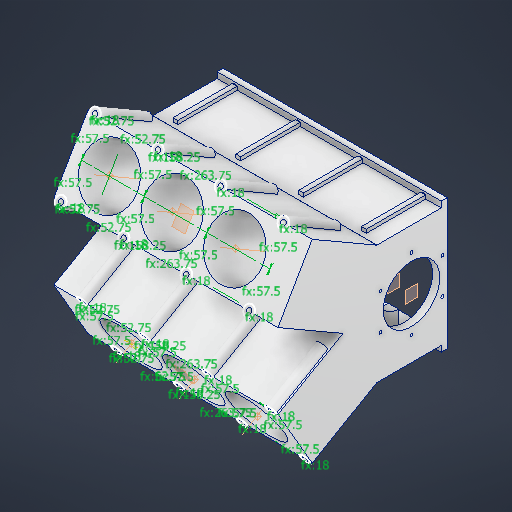
# Autodesk Inventor part: V6_Engine_Block
Saved by Autodesk Inventor 2027.1 (Build 311270010, 270A)
## iProperties
Created: 2026-10-17
Part Number: V6_Engine_Block
Material: Aluminum 6061
Document SubType Name: Modeling
Designer: kashyap
Density: 2.7 g/cm^3
Appearance: Aluminum - Flat
Mass: 21901.2 g
Surface Area: 10450.8 cm^2
Volume: 8111.54 cm^3
Material_Status: Assumed for this reconstruction
Author: kashyap
Autodesk Inventor part; units mm, degrees
ref_plane "YZ Plane" through (0, 0, 0) normal (1, 0, 0) x (0, 1, 0)
derived "V6_Engine_Master.ipt"
ref_plane "Bank_A_Plane" through (0, 0, 0) normal (0, 0.8660254, -0.5) x (-1, 0, 0)
ref_plane "Bank_B_Plane" through (0, 0, 0) normal (0, 0.8660254, 0.5) x (-1, 0, 0)
ref_plane "Bank_A_Perp_Plane" through (0, 0, 0) normal (0, 0.5, 0.8660254) x (-1, 0, 0)
ref_plane "Bank_B_Perp_Plane" through (0, 0, 0) normal (0, -0.5, 0.8660254) x (-1, 0, 0)
ref_plane "Bank_A_Deck_Plane" through (0, 112.9, 195.5485) normal (0, 0.5, 0.8660254) x (-1, 0, 0)
ref_plane "Bank_B_Deck_Plane" through (0, -112.9, 195.5485) normal (0, -0.5, 0.8660254) x (-1, 0, 0)
ref_plane "Cyl_A1_Station_Plane" through (-123.8, 0, 0) normal (1, 0, 0) x (0, 1, 0)
ref_plane "Cyl_A2_Station_Plane" through (-18.3, 0, 0) normal (1, 0, 0) x (0, 1, 0)
ref_plane "Cyl_A3_Station_Plane" through (87.2, 0, 0) normal (1, 0, 0) x (0, 1, 0)
ref_plane "Cyl_B1_Station_Plane" through (-87.2, 0, 0) normal (1, 0, 0) x (0, 1, 0)
ref_plane "Cyl_B2_Station_Plane" through (18.3, 0, 0) normal (1, 0, 0) x (0, 1, 0)
ref_plane "Cyl_B3_Station_Plane" through (123.8, 0, 0) normal (1, 0, 0) x (0, 1, 0)
ref_plane "Main_Bearing_Station_1" through (-158.25, 0, 0) normal (1, 0, 0) x (0, 1, 0)
ref_plane "Main_Bearing_Station_2" through (-52.75, 0, 0) normal (1, 0, 0) x (0, 1, 0)
ref_plane "Main_Bearing_Station_3" through (52.75, 0, 0) normal (1, 0, 0) x (0, 1, 0)
ref_plane "Main_Bearing_Station_4" through (158.25, 0, 0) normal (1, 0, 0) x (0, 1, 0)
ref_plane "Front_Interface" through (-188.25, 0, 0) normal (1, 0, 0) x (0, 1, 0)
ref_plane "Rear_Interface" through (188.25, 0, 0) normal (1, 0, 0) x (0, 1, 0)
ref_plane "Oil_Pan_Plane" through (0, 0, -60) normal (0, 0, 1) x (1, 0, 0)
sketch "SK_Bank_A_Prism" plane through (-188.25, 0, 0) normal (1, 0, 0) x (0, 1, 0)
  line L0 (170.3375, 295.0332) -> (-57.4375, -99.4847) construction
  line L1 (-188.26, 108.692) -> (188.26, -108.692) construction
  line L2 (-75.36, 304.2405) -> (301.16, 86.8565) construction
  line L3 (49.7965, -28.75) -> (162.6965, 166.7985)
  line L4 (162.6965, 166.7985) -> (63.1035, 224.2985)
  line L5 (63.1035, 224.2985) -> (-49.7965, 28.75)
  line L6 (-49.7965, 28.75) -> (49.7965, -28.75)
  dimension "d19" = 57.5
  dimension "d20" = 57.5
  constraints: 8 end point, 2 collinear, 2 parallel
  measures "d19" distance between parallel lines of L3 L0
  measures "d20" distance between parallel lines of L5 L0
extrude "Bank_A_Prism" add sketch "SK_Bank_A_Prism" along normal up to surface (376.5 mm away)
sketch "SK_Bank_B_Prism" plane through (-188.25, 0, 0) normal (1, 0, 0) x (0, 1, 0)
  line L0 (-170.3375, 295.0332) -> (57.4375, -99.4847) construction
  line L1 (-188.26, -108.692) -> (188.26, 108.692) construction
  line L2 (-301.16, 86.8565) -> (75.36, 304.2405) construction
  line L3 (-49.7965, -28.75) -> (-162.6965, 166.7985)
  line L4 (-162.6965, 166.7985) -> (-63.1035, 224.2985)
  line L5 (-63.1035, 224.2985) -> (49.7965, 28.75)
  line L6 (49.7965, 28.75) -> (-49.7965, -28.75)
  dimension "d23" = 57.5
  dimension "d24" = 57.5
  constraints: 8 end point, 2 collinear, 2 parallel
  measures "d23" distance between parallel lines of L3 L0
  measures "d24" distance between parallel lines of L5 L0
extrude "Bank_B_Prism" add sketch "SK_Bank_B_Prism" along normal up to surface (376.5 mm away)
sketch "SK_Crankcase_Prism" plane through (-188.25, 0, 0) normal (1, 0, 0) x (0, 1, 0)
  line L0 (-140, -60) -> (140, -60) construction
  line L1 (-100, -60) -> (100, -60)
  line L2 (100, -60) -> (100, 58)
  line L3 (100, 58) -> (-100, 58)
  line L4 (-100, 58) -> (-100, -60)
  point P0 (0, 0)
  dimension "d30" = 100
  dimension "d31" = 100
  dimension "d32" = 118
  constraints: 8 end point, 2 horizontal, 2 vertical, 1 collinear
  measures "d30" horizontal distance of point (0, 0) L1.end
  measures "d31" horizontal distance of point (0, 0) L3.end
  measures "d32" distance between parallel lines of L3 L0
extrude "Crankcase_Prism" add sketch "SK_Crankcase_Prism" along normal up to surface (376.5 mm away)
sketch "SK_Oil_Pan_Flange" plane through (-188.25, 0, 0) normal (1, 0, 0) x (0, 1, 0)
  line L0 (-154, -60) -> (154, -60) construction
  line L1 (-110, -60) -> (110, -60)
  line L2 (110, -60) -> (110, -50)
  line L3 (110, -50) -> (-110, -50)
  line L4 (-110, -50) -> (-110, -60)
  point P0 (0, 0)
  dimension "d35" = 110
  dimension "d36" = 110
  dimension "d37" = 10
  constraints: 8 end point, 2 horizontal, 2 vertical, 1 collinear
  measures "d35" horizontal distance of point (0, 0) L1.end
  measures "d36" horizontal distance of point (0, 0) L3.end
  measures "d37" distance between parallel lines of L3 L0
extrude "Oil_Pan_Flange" add sketch "SK_Oil_Pan_Flange" along normal up to surface (376.5 mm away)
ref_plane "Front_Wall_Inner_Plane" through (-176.25, 0, 0) normal (1, 0, 0) x (0, 1, 0)
ref_plane "Rear_Wall_Inner_Plane" through (176.25, 0, 0) normal (1, 0, 0) x (0, 1, 0)
sketch "SK_Cavity_Lower" plane through (-176.25, 0, 0) normal (1, 0, 0) x (0, 1, 0)
  line L0 (-131.6, -60) -> (131.6, -60) construction
  line L1 (-94, -60) -> (94, -60)
  line L2 (94, -60) -> (94, 45)
  line L3 (94, 45) -> (-94, 45)
  line L4 (-94, 45) -> (-94, -60)
  point P0 (0, 0)
  dimension "d42" = 94
  dimension "d43" = 94
  dimension "d44" = 105
  constraints: 8 end point, 2 horizontal, 2 vertical, 1 collinear
  measures "d42" horizontal distance of point (0, 0) L1.end
  measures "d43" horizontal distance of point (0, 0) L3.end
  measures "d44" distance between parallel lines of L3 L0
extrude "Cavity_Lower" cut sketch "SK_Cavity_Lower" along normal up to surface (352.5 mm away)
sketch "SK_Cavity_Under_Bank_A" plane through (-176.25, 0, 0) normal (1, 0, 0) x (0, 1, 0)
  line L0 (82.9722, 143.7121) -> (-37.5722, -65.077) construction
  line L1 (-104.6545, 60.4223) -> (104.6545, -60.4223) construction
  line L2 (40.7032, -23.5) -> (86.1032, 55.1351)
  line L3 (86.1032, 55.1351) -> (4.6968, 102.1351)
  line L4 (4.6968, 102.1351) -> (-40.7032, 23.5)
  line L5 (-40.7032, 23.5) -> (40.7032, -23.5)
  dimension "d47" = 47
  dimension "d48" = 47
  dimension "d49" = 90.8
  constraints: 8 end point, 3 parallel, 1 collinear
  measures "d47" distance between parallel lines of L2 L0
  measures "d48" distance between parallel lines of L4 L0
  measures "d49" distance between parallel lines of L3 L1
extrude "Cavity_Under_Bank_A" cut sketch "SK_Cavity_Under_Bank_A" along normal up to surface (352.5 mm away)
sketch "SK_Cavity_Under_Bank_B" plane through (-176.25, 0, 0) normal (1, 0, 0) x (0, 1, 0)
  line L0 (-82.9722, 143.7121) -> (37.5722, -65.077) construction
  line L1 (-104.6545, -60.4223) -> (104.6545, 60.4223) construction
  line L2 (-40.7032, -23.5) -> (-86.1032, 55.1351)
  line L3 (-86.1032, 55.1351) -> (-4.6968, 102.1351)
  line L4 (-4.6968, 102.1351) -> (40.7032, 23.5)
  line L5 (40.7032, 23.5) -> (-40.7032, -23.5)
  dimension "d52" = 47
  dimension "d53" = 47
  dimension "d54" = 90.8
  constraints: 8 end point, 3 parallel, 1 collinear
  measures "d52" distance between parallel lines of L2 L0
  measures "d53" distance between parallel lines of L4 L0
  measures "d54" distance between parallel lines of L3 L1
extrude "Cavity_Under_Bank_B" cut sketch "SK_Cavity_Under_Bank_B" along normal up to surface (352.5 mm away)
sketch "SK_Main_Web_1" plane through (-158.25, 0, 0) normal (1, 0, 0) x (0, 1, 0)
  line L0 (-131.6, 0) -> (131.6, 0) construction
  line L1 (-94, 0) -> (-33.015, 0)
  line L2 (33.015, 0) -> (94, 0)
  line L3 (94, 0) -> (94, 110)
  line L4 (94, 110) -> (-94, 110)
  line L5 (-94, 110) -> (-94, 0)
  arc A0 (33.015, 0) -> (-33.015, 0) centre (0, 0) ccw
  dimension "d57" = 33.015
  dimension "d58" = 94
  dimension "d59" = 94
  dimension "d60" = 110
  constraints: 10 end point, 2 collinear, 2 point on circle, 2 vertical, 1 centre point, 1 coincident, 1 horizontal
  measures "d57" radius of A0
  measures "d58" distance of point (0, 0) L2.end
  measures "d59" distance of point (0, 0) L1.start
  measures "d60" distance between parallel lines of L4 L0
extrude "Main_Web_1" add sketch "SK_Main_Web_1" along normal mid plane 17
sketch "SK_Main_Web_2" plane through (-52.75, 0, 0) normal (1, 0, 0) x (0, 1, 0)
  line L0 (-131.6, 0) -> (131.6, 0) construction
  line L1 (-94, 0) -> (-33.015, 0)
  line L2 (33.015, 0) -> (94, 0)
  line L3 (94, 0) -> (94, 110)
  line L4 (94, 110) -> (-94, 110)
  line L5 (-94, 110) -> (-94, 0)
  arc A0 (33.015, 0) -> (-33.015, 0) centre (0, 0) ccw
  dimension "d63" = 33.015
  dimension "d64" = 94
  dimension "d65" = 94
  dimension "d66" = 110
  constraints: 10 end point, 2 collinear, 2 point on circle, 2 vertical, 1 centre point, 1 coincident, 1 horizontal
  measures "d63" radius of A0
  measures "d64" distance of point (0, 0) L2.end
  measures "d65" distance of point (0, 0) L1.start
  measures "d66" distance between parallel lines of L4 L0
extrude "Main_Web_2" add sketch "SK_Main_Web_2" along normal mid plane 17
sketch "SK_Main_Web_3" plane through (52.75, 0, 0) normal (1, 0, 0) x (0, 1, 0)
  line L0 (-131.6, 0) -> (131.6, 0) construction
  line L1 (-94, 0) -> (-33.015, 0)
  line L2 (33.015, 0) -> (94, 0)
  line L3 (94, 0) -> (94, 110)
  line L4 (94, 110) -> (-94, 110)
  line L5 (-94, 110) -> (-94, 0)
  arc A0 (33.015, 0) -> (-33.015, 0) centre (0, 0) ccw
  dimension "d69" = 33.015
  dimension "d70" = 94
  dimension "d71" = 94
  dimension "d72" = 110
  constraints: 10 end point, 2 collinear, 2 point on circle, 2 vertical, 1 centre point, 1 coincident, 1 horizontal
  measures "d69" radius of A0
  measures "d70" distance of point (0, 0) L2.end
  measures "d71" distance of point (0, 0) L1.start
  measures "d72" distance between parallel lines of L4 L0
extrude "Main_Web_3" add sketch "SK_Main_Web_3" along normal mid plane 17
sketch "SK_Main_Web_4" plane through (158.25, 0, 0) normal (1, 0, 0) x (0, 1, 0)
  line L0 (-131.6, 0) -> (131.6, 0) construction
  line L1 (-94, 0) -> (-33.015, 0)
  line L2 (33.015, 0) -> (94, 0)
  line L3 (94, 0) -> (94, 110)
  line L4 (94, 110) -> (-94, 110)
  line L5 (-94, 110) -> (-94, 0)
  arc A0 (33.015, 0) -> (-33.015, 0) centre (0, 0) ccw
  dimension "d75" = 33.015
  dimension "d76" = 94
  dimension "d77" = 94
  dimension "d78" = 110
  constraints: 10 end point, 2 collinear, 2 point on circle, 2 vertical, 1 centre point, 1 coincident, 1 horizontal
  measures "d75" radius of A0
  measures "d76" distance of point (0, 0) L2.end
  measures "d77" distance of point (0, 0) L1.start
  measures "d78" distance between parallel lines of L4 L0
extrude "Main_Web_4" add sketch "SK_Main_Web_4" along normal mid plane 17
sketch "SK_Bores_Bank_A" plane through (-18.3, 112.9, 195.5485) normal (0, 0.5, 0.8660254) x (1, 0, 0)
  circle A0 centre (-105.5, 0) radius 47
  circle A1 centre (0, 0) radius 47
  circle A2 centre (105.5, 0) radius 47
  dimension "d81" = 94
  dimension "d82" = 94
  dimension "d83" = 94
  constraints: 3 centre point, 3 coincident
  measures "d81" diameter of A0
  measures "d82" diameter of A1
  measures "d83" diameter of A2
extrude "Bores_Bank_A" cut sketch "SK_Bores_Bank_A" against normal blind 150
sketch "SK_Bores_Bank_B" plane through (18.3, -112.9, 195.5485) normal (0, -0.5, 0.8660254) x (1, 0, 0)
  circle A0 centre (-105.5, 0) radius 47
  circle A1 centre (0, 0) radius 47
  circle A2 centre (105.5, 0) radius 47
  dimension "d86" = 94
  dimension "d87" = 94
  dimension "d88" = 94
  constraints: 3 centre point, 3 coincident
  measures "d86" diameter of A0
  measures "d87" diameter of A1
  measures "d88" diameter of A2
extrude "Bores_Bank_B" cut sketch "SK_Bores_Bank_B" against normal blind 150
sketch "SK_Head_Bolts_Bank_A" plane through (-18.3, 112.9, 195.5485) normal (0, 0.5, 0.8660254) x (1, 0, 0)
  circle A0 centre (-158.25, 57.5) radius 9
  circle A1 centre (-158.25, -57.5) radius 9
  circle A2 centre (-52.75, 57.5) radius 9
  circle A3 centre (-52.75, -57.5) radius 9
  circle A4 centre (52.75, 57.5) radius 9
  circle A5 centre (52.75, -57.5) radius 9
  circle A6 centre (158.25, 57.5) radius 9
  circle A7 centre (158.25, -57.5) radius 9
  point P0 (-105.5, 0)
  dimension "d93" = 18
  dimension "d96" = 18
  dimension "d99" = 18
  dimension "d102" = 18
  dimension "d105" = 18
  dimension "d108" = 18
  dimension "d111" = 18
  dimension "d114" = 18
  dimension "d157" = 52.75
  dimension "d158" = 57.5
  dimension "d159" = 52.75
  dimension "d160" = 57.5
  dimension "d161" = 52.75
  dimension "d162" = 57.5
  dimension "d163" = 52.75
  dimension "d164" = 57.5
  dimension "d165" = 158.25
  dimension "d166" = 57.5
  dimension "d167" = 158.25
  dimension "d168" = 57.5
  dimension "d169" = 263.75
  dimension "d170" = 57.5
  dimension "d171" = 263.75
  dimension "d172" = 57.5
  constraints: 8 centre point
  measures "d93" diameter of A0
  measures "d96" diameter of A1
  measures "d99" diameter of A2
  measures "d102" diameter of A3
  measures "d105" diameter of A4
  measures "d108" diameter of A5
  measures "d111" diameter of A6
  measures "d114" diameter of A7
  measures "d157" horizontal distance of point (-105.5, 0) A0.centre
  measures "d158" vertical distance of point (-105.5, 0) A0.centre
  measures "d159" horizontal distance of point (-105.5, 0) A1.centre
  measures "d160" vertical distance of point (-105.5, 0) A1.centre
  measures "d161" horizontal distance of point (-105.5, 0) A2.centre
  measures "d162" vertical distance of point (-105.5, 0) A2.centre
  measures "d163" horizontal distance of point (-105.5, 0) A3.centre
  measures "d164" vertical distance of point (-105.5, 0) A3.centre
  measures "d165" horizontal distance of point (-105.5, 0) A4.centre
  measures "d166" vertical distance of point (-105.5, 0) A4.centre
  measures "d167" horizontal distance of point (-105.5, 0) A5.centre
  measures "d168" vertical distance of point (-105.5, 0) A5.centre
  measures "d169" horizontal distance of point (-105.5, 0) A6.centre
  measures "d170" vertical distance of point (-105.5, 0) A6.centre
  measures "d171" horizontal distance of point (-105.5, 0) A7.centre
  measures "d172" vertical distance of point (-105.5, 0) A7.centre
extrude "Head_Bolt_Bosses_Bank_A" add sketch "SK_Head_Bolts_Bank_A" against normal blind 100
sketch "SK_Head_Bolts_Bank_B" plane through (18.3, -112.9, 195.5485) normal (0, -0.5, 0.8660254) x (1, 0, 0)
  circle A0 centre (-158.25, -57.5) radius 9
  circle A1 centre (-158.25, 57.5) radius 9
  circle A2 centre (-52.75, -57.5) radius 9
  circle A3 centre (-52.75, 57.5) radius 9
  circle A4 centre (52.75, -57.5) radius 9
  circle A5 centre (52.75, 57.5) radius 9
  circle A6 centre (158.25, -57.5) radius 9
  circle A7 centre (158.25, 57.5) radius 9
  point P0 (-105.5, 0)
  dimension "d126" = 18
  dimension "d129" = 18
  dimension "d132" = 18
  dimension "d135" = 18
  dimension "d138" = 18
  dimension "d141" = 18
  dimension "d144" = 18
  dimension "d147" = 18
  dimension "d196" = 52.75
  dimension "d197" = 57.5
  dimension "d198" = 52.75
  dimension "d199" = 57.5
  dimension "d200" = 52.75
  dimension "d201" = 57.5
  dimension "d202" = 52.75
  dimension "d203" = 57.5
  dimension "d204" = 158.25
  dimension "d205" = 57.5
  dimension "d206" = 158.25
  dimension "d207" = 57.5
  dimension "d208" = 263.75
  dimension "d209" = 57.5
  dimension "d210" = 263.75
  dimension "d211" = 57.5
  constraints: 8 centre point
  measures "d126" diameter of A0
  measures "d129" diameter of A1
  measures "d132" diameter of A2
  measures "d135" diameter of A3
  measures "d138" diameter of A4
  measures "d141" diameter of A5
  measures "d144" diameter of A6
  measures "d147" diameter of A7
  measures "d196" horizontal distance of point (-105.5, 0) A0.centre
  measures "d197" vertical distance of point (-105.5, 0) A0.centre
  measures "d198" horizontal distance of point (-105.5, 0) A1.centre
  measures "d199" vertical distance of point (-105.5, 0) A1.centre
  measures "d200" horizontal distance of point (-105.5, 0) A2.centre
  measures "d201" vertical distance of point (-105.5, 0) A2.centre
  measures "d202" horizontal distance of point (-105.5, 0) A3.centre
  measures "d203" vertical distance of point (-105.5, 0) A3.centre
  measures "d204" horizontal distance of point (-105.5, 0) A4.centre
  measures "d205" vertical distance of point (-105.5, 0) A4.centre
  measures "d206" horizontal distance of point (-105.5, 0) A5.centre
  measures "d207" vertical distance of point (-105.5, 0) A5.centre
  measures "d208" horizontal distance of point (-105.5, 0) A6.centre
  measures "d209" vertical distance of point (-105.5, 0) A6.centre
  measures "d210" horizontal distance of point (-105.5, 0) A7.centre
  measures "d211" vertical distance of point (-105.5, 0) A7.centre
extrude "Head_Bolt_Bosses_Bank_B" add sketch "SK_Head_Bolts_Bank_B" against normal blind 100
sketch "SK_Head_Bolt_Holes_Bank_A" plane through (-18.3, 112.9, 195.5485) normal (0, 0.5, 0.8660254) x (1, 0, 0)
  point P0 (-105.5, 0)
  point P1 (-158.25, 57.5)
  point P2 (-158.25, -57.5)
  point P3 (-52.75, 57.5)
  point P4 (-52.75, -57.5)
  point P5 (52.75, 57.5)
  point P6 (52.75, -57.5)
  point P7 (158.25, 57.5)
  point P8 (158.25, -57.5)
  dimension "d256" = 52.75
  dimension "d257" = 57.5
  dimension "d258" = 52.75
  dimension "d259" = 57.5
  dimension "d260" = 52.75
  dimension "d261" = 57.5
  dimension "d262" = 52.75
  dimension "d263" = 57.5
  dimension "d264" = 158.25
  dimension "d265" = 57.5
  dimension "d266" = 158.25
  dimension "d267" = 57.5
  dimension "d268" = 263.75
  dimension "d269" = 57.5
  dimension "d270" = 263.75
  dimension "d271" = 57.5
  measures "d256" horizontal distance of point (-105.5, 0) point (-158.25, 57.5)
  measures "d257" vertical distance of point (-105.5, 0) point (-158.25, 57.5)
  measures "d258" horizontal distance of point (-105.5, 0) point (-158.25, -57.5)
  measures "d259" vertical distance of point (-105.5, 0) point (-158.25, -57.5)
  measures "d260" horizontal distance of point (-105.5, 0) point (-52.75, 57.5)
  measures "d261" vertical distance of point (-105.5, 0) point (-52.75, 57.5)
  measures "d262" horizontal distance of point (-105.5, 0) point (-52.75, -57.5)
  measures "d263" vertical distance of point (-105.5, 0) point (-52.75, -57.5)
  measures "d264" horizontal distance of point (-105.5, 0) point (52.75, 57.5)
  measures "d265" vertical distance of point (-105.5, 0) point (52.75, 57.5)
  measures "d266" horizontal distance of point (-105.5, 0) point (52.75, -57.5)
  measures "d267" vertical distance of point (-105.5, 0) point (52.75, -57.5)
  measures "d268" horizontal distance of point (-105.5, 0) point (158.25, 57.5)
  measures "d269" vertical distance of point (-105.5, 0) point (158.25, 57.5)
  measures "d270" horizontal distance of point (-105.5, 0) point (158.25, -57.5)
  measures "d271" vertical distance of point (-105.5, 0) point (158.25, -57.5)
hole "Head_Bolt_Holes_Bank_A" at (-176.55, 162.6965, 166.7985) at (-176.55, 63.1035, 224.2985) at (-71.05, 162.6965, 166.7985) at (-71.05, 63.1035, 224.2985) at (34.45, 162.6965, 166.7985) at (34.45, 63.1035, 224.2985) at (139.95, 162.6965, 166.7985) at (139.95, 63.1035, 224.2985) direction (0, -0.5, -0.8660254) diameter 8.5 depth 90
sketch "SK_Head_Bolt_Holes_Bank_B" plane through (18.3, -112.9, 195.5485) normal (0, -0.5, 0.8660254) x (1, 0, 0)
  point P0 (-105.5, 0)
  point P1 (-158.25, -57.5)
  point P2 (-158.25, 57.5)
  point P3 (-52.75, -57.5)
  point P4 (-52.75, 57.5)
  point P5 (52.75, -57.5)
  point P6 (52.75, 57.5)
  point P7 (158.25, -57.5)
  point P8 (158.25, 57.5)
  dimension "d279" = 52.75
  dimension "d280" = 57.5
  dimension "d281" = 52.75
  dimension "d282" = 57.5
  dimension "d283" = 52.75
  dimension "d284" = 57.5
  dimension "d285" = 52.75
  dimension "d286" = 57.5
  dimension "d287" = 158.25
  dimension "d288" = 57.5
  dimension "d289" = 158.25
  dimension "d290" = 57.5
  dimension "d291" = 263.75
  dimension "d292" = 57.5
  dimension "d293" = 263.75
  dimension "d294" = 57.5
  measures "d279" horizontal distance of point (-105.5, 0) point (-158.25, -57.5)
  measures "d280" vertical distance of point (-105.5, 0) point (-158.25, -57.5)
  measures "d281" horizontal distance of point (-105.5, 0) point (-158.25, 57.5)
  measures "d282" vertical distance of point (-105.5, 0) point (-158.25, 57.5)
  measures "d283" horizontal distance of point (-105.5, 0) point (-52.75, -57.5)
  measures "d284" vertical distance of point (-105.5, 0) point (-52.75, -57.5)
  measures "d285" horizontal distance of point (-105.5, 0) point (-52.75, 57.5)
  measures "d286" vertical distance of point (-105.5, 0) point (-52.75, 57.5)
  measures "d287" horizontal distance of point (-105.5, 0) point (52.75, -57.5)
  measures "d288" vertical distance of point (-105.5, 0) point (52.75, -57.5)
  measures "d289" horizontal distance of point (-105.5, 0) point (52.75, 57.5)
  measures "d290" vertical distance of point (-105.5, 0) point (52.75, 57.5)
  measures "d291" horizontal distance of point (-105.5, 0) point (158.25, -57.5)
  measures "d292" vertical distance of point (-105.5, 0) point (158.25, -57.5)
  measures "d293" horizontal distance of point (-105.5, 0) point (158.25, 57.5)
  measures "d294" vertical distance of point (-105.5, 0) point (158.25, 57.5)
hole "Head_Bolt_Holes_Bank_B" at (-139.95, -162.6965, 166.7985) at (-139.95, -63.1035, 224.2985) at (-34.45, -162.6965, 166.7985) at (-34.45, -63.1035, 224.2985) at (71.05, -162.6965, 166.7985) at (71.05, -63.1035, 224.2985) at (176.55, -162.6965, 166.7985) at (176.55, -63.1035, 224.2985) direction (0, 0.5, -0.8660254) diameter 8.5 depth 90
sketch "SK_Main_Cap_Bolt_Holes" plane through (0, 0, 0) normal (0, 0, 1) x (1, 0, 0)
  line L0 (-158.25, 61.6) -> (-158.25, -61.6) construction
  line L1 (-52.75, 61.6) -> (-52.75, -61.6) construction
  line L2 (52.75, 61.6) -> (52.75, -61.6) construction
  line L3 (158.25, 61.6) -> (158.25, -61.6) construction
  point P0 (0, 0)
  point P1 (-158.25, 44)
  point P2 (-158.25, -44)
  point P3 (-52.75, 44)
  point P4 (-52.75, -44)
  point P5 (52.75, 44)
  point P6 (52.75, -44)
  point P7 (158.25, 44)
  point P8 (158.25, -44)
  dimension "d302" = 44
  dimension "d303" = 44
  dimension "d304" = 44
  dimension "d305" = 44
  dimension "d306" = 44
  dimension "d307" = 44
  dimension "d308" = 44
  dimension "d309" = 44
  constraints: 8 point on line
  measures "d302" vertical distance of point (0, 0) point (-158.25, 44)
  measures "d303" vertical distance of point (0, 0) point (-158.25, -44)
  measures "d304" vertical distance of point (0, 0) point (-52.75, 44)
  measures "d305" vertical distance of point (0, 0) point (-52.75, -44)
  measures "d306" vertical distance of point (0, 0) point (52.75, 44)
  measures "d307" vertical distance of point (0, 0) point (52.75, -44)
  measures "d308" vertical distance of point (0, 0) point (158.25, 44)
  measures "d309" vertical distance of point (0, 0) point (158.25, -44)
hole "Main_Cap_Bolt_Holes" at (-158.25, 44, 0) at (-158.25, -44, 0) at (-52.75, 44, 0) at (-52.75, -44, 0) at (52.75, 44, 0) at (52.75, -44, 0) at (158.25, 44, 0) at (158.25, -44, 0) direction (0, 0, 1) diameter 8.5 depth 50
sketch "SK_Oil_Pan_Bolt_Holes" plane through (0, 0, -60) normal (0, 0, 1) x (1, 0, 0)
  line L0 (-158.25, 147) -> (-158.25, -147) construction
  line L1 (-52.75, 147) -> (-52.75, -147) construction
  line L2 (52.75, 147) -> (52.75, -147) construction
  line L3 (158.25, 147) -> (158.25, -147) construction
  point P0 (0, 0)
  point P1 (-158.25, 105)
  point P2 (-158.25, -105)
  point P3 (-52.75, 105)
  point P4 (-52.75, -105)
  point P5 (52.75, 105)
  point P6 (52.75, -105)
  point P7 (158.25, 105)
  point P8 (158.25, -105)
  dimension "d324" = 105
  dimension "d325" = 105
  dimension "d326" = 105
  dimension "d327" = 105
  dimension "d328" = 105
  dimension "d329" = 105
  dimension "d330" = 105
  dimension "d331" = 105
  constraints: 8 point on line
  measures "d324" vertical distance of point (0, 0) point (-158.25, 105)
  measures "d325" vertical distance of point (0, 0) point (-158.25, -105)
  measures "d326" vertical distance of point (0, 0) point (-52.75, 105)
  measures "d327" vertical distance of point (0, 0) point (-52.75, -105)
  measures "d328" vertical distance of point (0, 0) point (52.75, 105)
  measures "d329" vertical distance of point (0, 0) point (52.75, -105)
  measures "d330" vertical distance of point (0, 0) point (158.25, 105)
  measures "d331" vertical distance of point (0, 0) point (158.25, -105)
hole "Oil_Pan_Bolt_Holes" at (-158.25, 105, -60) at (-158.25, -105, -60) at (-52.75, 105, -60) at (-52.75, -105, -60) at (52.75, 105, -60) at (52.75, -105, -60) at (158.25, 105, -60) at (158.25, -105, -60) direction (0, 0, 1) diameter 5 depth 10
sketch "SK_Front_Crank_Opening" plane through (-188.25, 0, 0) normal (1, 0, 0) x (0, 1, 0)
  circle A0 centre (0, 0) radius 35
  dimension "d346" = 70
  constraints: 1 centre point, 1 coincident
  measures "d346" diameter of A0
extrude "Front_Crank_Opening" cut sketch "SK_Front_Crank_Opening" along normal blind 12
sketch "SK_Front_Crank_Opening_Bolt_Holes" plane through (-188.25, 0, 0) normal (1, 0, 0) x (0, 1, 0)
  line L0 (0, 0) -> (0, 100) construction
  point P0 (80, -45)
  point P1 (-80, -45)
  point P2 (80, 30)
  point P3 (-80, 30)
  point P4 (100, 173.2)
  point P5 (-100, 173.2)
  dimension "d349" = 80
  dimension "d350" = 45
  dimension "d351" = 80
  dimension "d352" = 45
  dimension "d353" = 80
  dimension "d354" = 30
  dimension "d355" = 80
  dimension "d356" = 30
  dimension "d357" = 100
  dimension "d358" = 100
  dimension "d359" = 173.2
  dimension "d360" = 100
  dimension "d361" = 173.2
  constraints: 2 end point, 1 vertical
  measures "d349" horizontal distance of L0.start point (80, -45)
  measures "d350" vertical distance of L0.start point (80, -45)
  measures "d351" horizontal distance of L0.start point (-80, -45)
  measures "d352" vertical distance of L0.start point (-80, -45)
  measures "d353" horizontal distance of L0.start point (80, 30)
  measures "d354" vertical distance of L0.start point (80, 30)
  measures "d355" horizontal distance of L0.start point (-80, 30)
  measures "d356" vertical distance of L0.start point (-80, 30)
  measures "d357" distance of L0.start L0.end
  measures "d358" horizontal distance of L0.start point (100, 173.2)
  measures "d359" vertical distance of L0.start point (100, 173.2)
  measures "d360" horizontal distance of L0.start point (-100, 173.2)
  measures "d361" vertical distance of L0.start point (-100, 173.2)
hole "Front_Crank_Opening_Bolt_Holes" at (-188.25, 80, -45) at (-188.25, -80, -45) at (-188.25, 80, 30) at (-188.25, -80, 30) at (-188.25, 0, 100) at (-188.25, 100, 173.2) at (-188.25, -100, 173.2) direction (1, 0, 0) diameter 5 depth 10
sketch "SK_Rear_Seal_Bore" plane through (188.25, 0, 0) normal (1, 0, 0) x (0, 1, 0)
  circle A0 centre (0, 0) radius 47.5
  dimension "d376" = 95
  constraints: 1 centre point, 1 coincident
  measures "d376" diameter of A0
extrude "Rear_Seal_Bore" cut sketch "SK_Rear_Seal_Bore" against normal blind 12
sketch "SK_Rear_Seal_Bore_Bolt_Holes" plane through (188.25, 0, 0) normal (1, 0, 0) x (0, 1, 0)
  point P0 (0, 0)
  point P1 (60, 0)
  point P2 (-60, 0)
  point P3 (30, 51.9615)
  point P4 (-30, 51.9615)
  point P5 (30, -51.9615)
  point P6 (-30, -51.9615)
  dimension "d381" = 60
  dimension "d382" = 0
  dimension "d383" = 60
  dimension "d384" = 0
  dimension "d385" = 30
  dimension "d386" = 51.9615
  dimension "d387" = 30
  dimension "d388" = 51.9615
  dimension "d389" = 30
  dimension "d390" = 51.9615
  dimension "d391" = 30
  dimension "d392" = 51.9615
  measures "d381" distance of point (0, 0) point (60, 0)
  measures "d382" vertical distance of point (0, 0) point (60, 0)
  measures "d383" distance of point (0, 0) point (-60, 0)
  measures "d384" vertical distance of point (0, 0) point (-60, 0)
  measures "d385" horizontal distance of point (0, 0) point (30, 51.962)
  measures "d386" vertical distance of point (0, 0) point (30, 51.962)
  measures "d387" horizontal distance of point (0, 0) point (-30, 51.962)
  measures "d388" vertical distance of point (0, 0) point (-30, 51.962)
  measures "d389" horizontal distance of point (0, 0) point (30, -51.962)
  measures "d390" vertical distance of point (0, 0) point (30, -51.962)
  measures "d391" horizontal distance of point (0, 0) point (-30, -51.962)
  measures "d392" vertical distance of point (0, 0) point (-30, -51.962)
hole "Rear_Seal_Bore_Bolt_Holes" at (188.25, 60, 0) at (188.25, -60, 0) at (188.25, 30, 51.9615) at (188.25, -30, 51.9615) at (188.25, 30, -51.9615) at (188.25, -30, -51.9615) direction (-1, 0, 0) diameter 5 depth 10
sketch "SK_Skirt_Ribs_1" plane through (-158.25, 0, 0) normal (1, 0, 0) x (0, 1, 0)
  line L0 (-148.4, -60) -> (148.4, -60) construction
  line L1 (100, -50) -> (106, -50)
  line L2 (106, -50) -> (106, 50)
  line L3 (106, 50) -> (100, 50)
  line L4 (100, 50) -> (100, -50)
  line L5 (-100, -50) -> (-106, -50)
  line L6 (-106, -50) -> (-106, 50)
  line L7 (-106, 50) -> (-100, 50)
  line L8 (-100, 50) -> (-100, -50)
  point P0 (0, 0)
  dimension "d400" = 10
  dimension "d401" = 110
  dimension "d402" = 100
  dimension "d403" = 106
  dimension "d404" = 10
  dimension "d405" = 110
  dimension "d406" = 100
  dimension "d407" = 106
  constraints: 16 end point, 4 horizontal, 4 vertical
  measures "d400" distance between parallel lines of L1 L0
  measures "d401" distance between parallel lines of L3 L0
  measures "d402" horizontal distance of point (0, 0) L3.end
  measures "d403" horizontal distance of point (0, 0) L1.end
  measures "d404" distance between parallel lines of L5 L0
  measures "d405" distance between parallel lines of L7 L0
  measures "d406" horizontal distance of point (0, 0) L7.end
  measures "d407" horizontal distance of point (0, 0) L5.end
extrude "Skirt_Ribs_1" add sketch "SK_Skirt_Ribs_1" along normal mid plane 8
sketch "SK_Skirt_Ribs_2" plane through (-52.75, 0, 0) normal (1, 0, 0) x (0, 1, 0)
  line L0 (-148.4, -60) -> (148.4, -60) construction
  line L1 (100, -50) -> (106, -50)
  line L2 (106, -50) -> (106, 50)
  line L3 (106, 50) -> (100, 50)
  line L4 (100, 50) -> (100, -50)
  line L5 (-100, -50) -> (-106, -50)
  line L6 (-106, -50) -> (-106, 50)
  line L7 (-106, 50) -> (-100, 50)
  line L8 (-100, 50) -> (-100, -50)
  point P0 (0, 0)
  dimension "d410" = 10
  dimension "d411" = 110
  dimension "d412" = 100
  dimension "d413" = 106
  dimension "d414" = 10
  dimension "d415" = 110
  dimension "d416" = 100
  dimension "d417" = 106
  constraints: 16 end point, 4 horizontal, 4 vertical
  measures "d410" distance between parallel lines of L1 L0
  measures "d411" distance between parallel lines of L3 L0
  measures "d412" horizontal distance of point (0, 0) L3.end
  measures "d413" horizontal distance of point (0, 0) L1.end
  measures "d414" distance between parallel lines of L5 L0
  measures "d415" distance between parallel lines of L7 L0
  measures "d416" horizontal distance of point (0, 0) L7.end
  measures "d417" horizontal distance of point (0, 0) L5.end
extrude "Skirt_Ribs_2" add sketch "SK_Skirt_Ribs_2" along normal mid plane 8
sketch "SK_Skirt_Ribs_3" plane through (52.75, 0, 0) normal (1, 0, 0) x (0, 1, 0)
  line L0 (-148.4, -60) -> (148.4, -60) construction
  line L1 (100, -50) -> (106, -50)
  line L2 (106, -50) -> (106, 50)
  line L3 (106, 50) -> (100, 50)
  line L4 (100, 50) -> (100, -50)
  line L5 (-100, -50) -> (-106, -50)
  line L6 (-106, -50) -> (-106, 50)
  line L7 (-106, 50) -> (-100, 50)
  line L8 (-100, 50) -> (-100, -50)
  point P0 (0, 0)
  dimension "d420" = 10
  dimension "d421" = 110
  dimension "d422" = 100
  dimension "d423" = 106
  dimension "d424" = 10
  dimension "d425" = 110
  dimension "d426" = 100
  dimension "d427" = 106
  constraints: 16 end point, 4 horizontal, 4 vertical
  measures "d420" distance between parallel lines of L1 L0
  measures "d421" distance between parallel lines of L3 L0
  measures "d422" horizontal distance of point (0, 0) L3.end
  measures "d423" horizontal distance of point (0, 0) L1.end
  measures "d424" distance between parallel lines of L5 L0
  measures "d425" distance between parallel lines of L7 L0
  measures "d426" horizontal distance of point (0, 0) L7.end
  measures "d427" horizontal distance of point (0, 0) L5.end
extrude "Skirt_Ribs_3" add sketch "SK_Skirt_Ribs_3" along normal mid plane 8
sketch "SK_Skirt_Ribs_4" plane through (158.25, 0, 0) normal (1, 0, 0) x (0, 1, 0)
  line L0 (-148.4, -60) -> (148.4, -60) construction
  line L1 (100, -50) -> (106, -50)
  line L2 (106, -50) -> (106, 50)
  line L3 (106, 50) -> (100, 50)
  line L4 (100, 50) -> (100, -50)
  line L5 (-100, -50) -> (-106, -50)
  line L6 (-106, -50) -> (-106, 50)
  line L7 (-106, 50) -> (-100, 50)
  line L8 (-100, 50) -> (-100, -50)
  point P0 (0, 0)
  dimension "d430" = 10
  dimension "d431" = 110
  dimension "d432" = 100
  dimension "d433" = 106
  dimension "d434" = 10
  dimension "d435" = 110
  dimension "d436" = 100
  dimension "d437" = 106
  constraints: 16 end point, 4 horizontal, 4 vertical
  measures "d430" distance between parallel lines of L1 L0
  measures "d431" distance between parallel lines of L3 L0
  measures "d432" horizontal distance of point (0, 0) L3.end
  measures "d433" horizontal distance of point (0, 0) L1.end
  measures "d434" distance between parallel lines of L5 L0
  measures "d435" distance between parallel lines of L7 L0
  measures "d436" horizontal distance of point (0, 0) L7.end
  measures "d437" horizontal distance of point (0, 0) L5.end
extrude "Skirt_Ribs_4" add sketch "SK_Skirt_Ribs_4" along normal mid plane 8
equation "\"d19\" = Bank_Half_Width"
equation "\"d20\" = Bank_Half_Width"
equation "\"d23\" = Bank_Half_Width"
equation "\"d24\" = Bank_Half_Width"
equation "\"d30\" = Skirt_Half_Width"
equation "\"d31\" = Skirt_Half_Width"
equation "\"d32\" = Oil_Pan_Rail_Depth + Crankcase_Top_Z"
equation "\"d35\" = Skirt_Half_Width + Pan_Flange_Width"
equation "\"d36\" = Skirt_Half_Width + Pan_Flange_Width"
equation "\"d37\" = Pan_Flange_Thickness"
equation "\"d42\" = Skirt_Half_Width - Skirt_Wall"
equation "\"d43\" = Skirt_Half_Width - Skirt_Wall"
equation "\"d44\" = Oil_Pan_Rail_Depth + Cavity_Rect_Top_Z"
equation "\"d47\" = 0.5 * Bore_Diameter"
equation "\"d48\" = 0.5 * Bore_Diameter"
equation "\"d49\" = Barrel_Bottom_H"
equation "\"d52\" = 0.5 * Bore_Diameter"
equation "\"d53\" = 0.5 * Bore_Diameter"
equation "\"d54\" = Barrel_Bottom_H"
equation "\"d57\" = 0.5 * Main_Housing_Bore"
equation "\"d58\" = Skirt_Half_Width - Skirt_Wall"
equation "\"d59\" = Skirt_Half_Width - Skirt_Wall"
equation "\"d60\" = Web_Top_Z"
equation "\"d61\" = Main_Web_Thickness"
equation "\"d63\" = 0.5 * Main_Housing_Bore"
equation "\"d64\" = Skirt_Half_Width - Skirt_Wall"
equation "\"d65\" = Skirt_Half_Width - Skirt_Wall"
equation "\"d66\" = Web_Top_Z"
equation "\"d67\" = Main_Web_Thickness"
equation "\"d69\" = 0.5 * Main_Housing_Bore"
equation "\"d70\" = Skirt_Half_Width - Skirt_Wall"
equation "\"d71\" = Skirt_Half_Width - Skirt_Wall"
equation "\"d72\" = Web_Top_Z"
equation "\"d73\" = Main_Web_Thickness"
equation "\"d75\" = 0.5 * Main_Housing_Bore"
equation "\"d76\" = Skirt_Half_Width - Skirt_Wall"
equation "\"d77\" = Skirt_Half_Width - Skirt_Wall"
equation "\"d78\" = Web_Top_Z"
equation "\"d79\" = Main_Web_Thickness"
equation "\"d81\" = Bore_Diameter"
equation "\"d82\" = Bore_Diameter"
equation "\"d83\" = Bore_Diameter"
equation "\"d84\" = Barrel_Length + Bore_Relief_Depth"
equation "\"d86\" = Bore_Diameter"
equation "\"d87\" = Bore_Diameter"
equation "\"d88\" = Bore_Diameter"
equation "\"d89\" = Barrel_Length + Bore_Relief_Depth"
equation "\"d93\" = Head_Bolt_Boss_Dia"
equation "\"d96\" = Head_Bolt_Boss_Dia"
equation "\"d99\" = Head_Bolt_Boss_Dia"
equation "\"d102\" = Head_Bolt_Boss_Dia"
equation "\"d105\" = Head_Bolt_Boss_Dia"
equation "\"d108\" = Head_Bolt_Boss_Dia"
equation "\"d111\" = Head_Bolt_Boss_Dia"
equation "\"d114\" = Head_Bolt_Boss_Dia"
equation "\"d157\" = 0.5 * Bore_Pitch"
equation "\"d158\" = Head_Bolt_Lateral_Offset"
equation "\"d159\" = 0.5 * Bore_Pitch"
equation "\"d160\" = Head_Bolt_Lateral_Offset"
equation "\"d161\" = 0.5 * Bore_Pitch"
equation "\"d162\" = Head_Bolt_Lateral_Offset"
equation "\"d163\" = 0.5 * Bore_Pitch"
equation "\"d164\" = Head_Bolt_Lateral_Offset"
equation "\"d165\" = 1.5 * Bore_Pitch"
equation "\"d166\" = Head_Bolt_Lateral_Offset"
equation "\"d167\" = 1.5 * Bore_Pitch"
equation "\"d168\" = Head_Bolt_Lateral_Offset"
equation "\"d169\" = 2.5 * Bore_Pitch"
equation "\"d170\" = Head_Bolt_Lateral_Offset"
equation "\"d171\" = 2.5 * Bore_Pitch"
equation "\"d172\" = Head_Bolt_Lateral_Offset"
equation "\"d115\" = Head_Bolt_Boss_Length"
equation "\"d126\" = Head_Bolt_Boss_Dia"
equation "\"d129\" = Head_Bolt_Boss_Dia"
equation "\"d132\" = Head_Bolt_Boss_Dia"
equation "\"d135\" = Head_Bolt_Boss_Dia"
equation "\"d138\" = Head_Bolt_Boss_Dia"
equation "\"d141\" = Head_Bolt_Boss_Dia"
equation "\"d144\" = Head_Bolt_Boss_Dia"
equation "\"d147\" = Head_Bolt_Boss_Dia"
equation "\"d196\" = 0.5 * Bore_Pitch"
equation "\"d197\" = Head_Bolt_Lateral_Offset"
equation "\"d198\" = 0.5 * Bore_Pitch"
equation "\"d199\" = Head_Bolt_Lateral_Offset"
equation "\"d200\" = 0.5 * Bore_Pitch"
equation "\"d201\" = Head_Bolt_Lateral_Offset"
equation "\"d202\" = 0.5 * Bore_Pitch"
equation "\"d203\" = Head_Bolt_Lateral_Offset"
equation "\"d204\" = 1.5 * Bore_Pitch"
equation "\"d205\" = Head_Bolt_Lateral_Offset"
equation "\"d206\" = 1.5 * Bore_Pitch"
equation "\"d207\" = Head_Bolt_Lateral_Offset"
equation "\"d208\" = 2.5 * Bore_Pitch"
equation "\"d209\" = Head_Bolt_Lateral_Offset"
equation "\"d210\" = 2.5 * Bore_Pitch"
equation "\"d211\" = Head_Bolt_Lateral_Offset"
equation "\"d148\" = Head_Bolt_Boss_Length"
equation "\"d256\" = 0.5 * Bore_Pitch"
equation "\"d257\" = Head_Bolt_Lateral_Offset"
equation "\"d258\" = 0.5 * Bore_Pitch"
equation "\"d259\" = Head_Bolt_Lateral_Offset"
equation "\"d260\" = 0.5 * Bore_Pitch"
equation "\"d261\" = Head_Bolt_Lateral_Offset"
equation "\"d262\" = 0.5 * Bore_Pitch"
equation "\"d263\" = Head_Bolt_Lateral_Offset"
equation "\"d264\" = 1.5 * Bore_Pitch"
equation "\"d265\" = Head_Bolt_Lateral_Offset"
equation "\"d266\" = 1.5 * Bore_Pitch"
equation "\"d267\" = Head_Bolt_Lateral_Offset"
equation "\"d268\" = 2.5 * Bore_Pitch"
equation "\"d269\" = Head_Bolt_Lateral_Offset"
equation "\"d270\" = 2.5 * Bore_Pitch"
equation "\"d271\" = Head_Bolt_Lateral_Offset"
equation "\"d272\" = Head_Bolt_Tap_Dia"
equation "\"d277\" = Head_Bolt_Hole_Depth"
equation "\"d279\" = 0.5 * Bore_Pitch"
equation "\"d280\" = Head_Bolt_Lateral_Offset"
equation "\"d281\" = 0.5 * Bore_Pitch"
equation "\"d282\" = Head_Bolt_Lateral_Offset"
equation "\"d283\" = 0.5 * Bore_Pitch"
equation "\"d284\" = Head_Bolt_Lateral_Offset"
equation "\"d285\" = 0.5 * Bore_Pitch"
equation "\"d286\" = Head_Bolt_Lateral_Offset"
equation "\"d287\" = 1.5 * Bore_Pitch"
equation "\"d288\" = Head_Bolt_Lateral_Offset"
equation "\"d289\" = 1.5 * Bore_Pitch"
equation "\"d290\" = Head_Bolt_Lateral_Offset"
equation "\"d291\" = 2.5 * Bore_Pitch"
equation "\"d292\" = Head_Bolt_Lateral_Offset"
equation "\"d293\" = 2.5 * Bore_Pitch"
equation "\"d294\" = Head_Bolt_Lateral_Offset"
equation "\"d295\" = Head_Bolt_Tap_Dia"
equation "\"d300\" = Head_Bolt_Hole_Depth"
equation "\"d302\" = Main_Cap_Bolt_Y"
equation "\"d303\" = Main_Cap_Bolt_Y"
equation "\"d304\" = Main_Cap_Bolt_Y"
equation "\"d305\" = Main_Cap_Bolt_Y"
equation "\"d306\" = Main_Cap_Bolt_Y"
equation "\"d307\" = Main_Cap_Bolt_Y"
equation "\"d308\" = Main_Cap_Bolt_Y"
equation "\"d309\" = Main_Cap_Bolt_Y"
equation "\"d317\" = Main_Cap_Bolt_Tap_Dia"
equation "\"d322\" = Main_Cap_Bolt_Depth"
equation "\"d324\" = Skirt_Half_Width + 0.5 * Pan_Flange_Width"
equation "\"d325\" = Skirt_Half_Width + 0.5 * Pan_Flange_Width"
equation "\"d326\" = Skirt_Half_Width + 0.5 * Pan_Flange_Width"
equation "\"d327\" = Skirt_Half_Width + 0.5 * Pan_Flange_Width"
equation "\"d328\" = Skirt_Half_Width + 0.5 * Pan_Flange_Width"
equation "\"d329\" = Skirt_Half_Width + 0.5 * Pan_Flange_Width"
equation "\"d330\" = Skirt_Half_Width + 0.5 * Pan_Flange_Width"
equation "\"d331\" = Skirt_Half_Width + 0.5 * Pan_Flange_Width"
equation "\"d339\" = Pan_Bolt_Tap_Dia"
equation "\"d344\" = Pan_Bolt_Depth"
equation "\"d346\" = Front_Crank_Opening_Dia"
equation "\"d347\" = End_Wall_Thickness"
equation "\"d369\" = Cover_Bolt_Tap_Dia"
equation "\"d374\" = Cover_Bolt_Depth"
equation "\"d376\" = Rear_Seal_Bore_Dia"
equation "\"d379\" = End_Wall_Thickness"
equation "\"d381\" = 0.5 * Rear_Seal_Bolt_PCD"
equation "\"d383\" = 0.5 * Rear_Seal_Bolt_PCD"
equation "\"d385\" = 0.25 * Rear_Seal_Bolt_PCD"
equation "\"d386\" = 0.433013 * Rear_Seal_Bolt_PCD"
equation "\"d387\" = 0.25 * Rear_Seal_Bolt_PCD"
equation "\"d388\" = 0.433013 * Rear_Seal_Bolt_PCD"
equation "\"d389\" = 0.25 * Rear_Seal_Bolt_PCD"
equation "\"d390\" = 0.433013 * Rear_Seal_Bolt_PCD"
equation "\"d391\" = 0.25 * Rear_Seal_Bolt_PCD"
equation "\"d392\" = 0.433013 * Rear_Seal_Bolt_PCD"
equation "\"d393\" = Cover_Bolt_Tap_Dia"
equation "\"d398\" = Cover_Bolt_Depth"
equation "\"d400\" = Pan_Flange_Thickness"
equation "\"d401\" = Oil_Pan_Rail_Depth + Rib_Top_Z"
equation "\"d402\" = Skirt_Half_Width"
equation "\"d403\" = Skirt_Half_Width + Rib_Height"
equation "\"d404\" = Pan_Flange_Thickness"
equation "\"d405\" = Oil_Pan_Rail_Depth + Rib_Top_Z"
equation "\"d406\" = Skirt_Half_Width"
equation "\"d407\" = Skirt_Half_Width + Rib_Height"
equation "\"d408\" = Rib_Thickness"
equation "\"d410\" = Pan_Flange_Thickness"
equation "\"d411\" = Oil_Pan_Rail_Depth + Rib_Top_Z"
equation "\"d412\" = Skirt_Half_Width"
equation "\"d413\" = Skirt_Half_Width + Rib_Height"
equation "\"d414\" = Pan_Flange_Thickness"
equation "\"d415\" = Oil_Pan_Rail_Depth + Rib_Top_Z"
equation "\"d416\" = Skirt_Half_Width"
equation "\"d417\" = Skirt_Half_Width + Rib_Height"
equation "\"d418\" = Rib_Thickness"
equation "\"d420\" = Pan_Flange_Thickness"
equation "\"d421\" = Oil_Pan_Rail_Depth + Rib_Top_Z"
equation "\"d422\" = Skirt_Half_Width"
equation "\"d423\" = Skirt_Half_Width + Rib_Height"
equation "\"d424\" = Pan_Flange_Thickness"
equation "\"d425\" = Oil_Pan_Rail_Depth + Rib_Top_Z"
equation "\"d426\" = Skirt_Half_Width"
equation "\"d427\" = Skirt_Half_Width + Rib_Height"
equation "\"d428\" = Rib_Thickness"
equation "\"d430\" = Pan_Flange_Thickness"
equation "\"d431\" = Oil_Pan_Rail_Depth + Rib_Top_Z"
equation "\"d432\" = Skirt_Half_Width"
equation "\"d433\" = Skirt_Half_Width + Rib_Height"
equation "\"d434\" = Pan_Flange_Thickness"
equation "\"d435\" = Oil_Pan_Rail_Depth + Rib_Top_Z"
equation "\"d436\" = Skirt_Half_Width"
equation "\"d437\" = Skirt_Half_Width + Rib_Height"
equation "\"d438\" = Rib_Thickness"
equation "\"Bank_Half_Width\" = 57.5"
equation "\"Oil_Pan_Rail_Depth\" = 60"
equation "\"Crankcase_Top_Z\" = 58"
equation "\"Pan_Flange_Thickness\" = 10"
equation "\"Cavity_Rect_Top_Z\" = 45"
equation "\"Bore_Diameter\" = 94"
equation "\"Barrel_Bottom_H\" = 90.8"
equation "\"Main_Housing_Bore\" = 66.03"
equation "\"Web_Top_Z\" = 110"
equation "\"Main_Web_Thickness\" = 17"
equation "\"Barrel_Length\" = 135"
equation "\"Bore_Relief_Depth\" = 15"
equation "\"Head_Bolt_Boss_Dia\" = 18"
equation "\"Head_Bolt_Boss_Length\" = 100"
equation "\"Head_Bolt_Tap_Dia\" = 8.5"
equation "\"Head_Bolt_Hole_Depth\" = 90"
equation "\"Main_Cap_Bolt_Tap_Dia\" = 8.5"
equation "\"Main_Cap_Bolt_Depth\" = 50"
equation "\"Pan_Bolt_Tap_Dia\" = 5"
equation "\"Pan_Bolt_Depth\" = 10"
equation "\"Front_Crank_Opening_Dia\" = 70"
equation "\"End_Wall_Thickness\" = 12"
equation "\"Cover_Bolt_Tap_Dia\" = 5"
equation "\"Cover_Bolt_Depth\" = 10"
equation "\"Rear_Seal_Bore_Dia\" = 95"
equation "\"Rib_Top_Z\" = 50"
equation "\"Rib_Thickness\" = 8"
equation "\"Skirt_Half_Width\" = 100"
equation "\"Pan_Flange_Width\" = 10"
equation "\"Skirt_Wall\" = 6"
equation "\"Bore_Pitch\" = 105.5"
equation "\"Head_Bolt_Lateral_Offset\" = 57.5"
equation "\"Main_Cap_Bolt_Y\" = 44"
equation "\"Rear_Seal_Bolt_PCD\" = 120"
equation "\"Rib_Height\" = 6"
body "Solid1"
